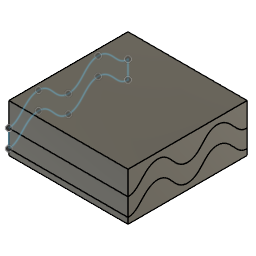
pressed block design v1 (Autodesk Fusion 360 design; units mm, degrees)
part number: 2026-06-01-15-53-17-386
Autodesk Fusion 360 part; units mm, degrees
sketch "basis" plane through (0, 0, 0) normal (1, 0, 0) x (0, 1, 0)
  spline S0 degree 5 poles (0, 0) (1.1772, 0) (3.4048, 0.3001) (6.3673, 1.6507) (9.7426, 4.9627) (13.9662, 10.0373) (18.9393, 14.1773) (25.064, 15.7986) (30.9233, 14.1773) (35.3862, 10.0373) (39.4218, 4.9627) (43.9948, 0.8227) (50, -0.7986) (56.0052, 0.8227) (60.5782, 4.9627) (64.6138, 10.0373) (69.0767, 14.1773) (74.936, 15.7986) (81.0607, 14.1773) (86.0338, 10.0373) (90.2574, 4.9627) (93.6327, 1.6507) (96.5952, 0.3001) (98.8228, 0) (100, 0) knots 0 0 0 0 0 0 0.05 0.1 0.15 0.2 0.25 0.3 0.35 0.4 0.45 0.5 0.55 0.6 0.65 0.7 0.75 0.8 0.85 0.9 0.95 1 1 1 1 1 1
  line L0 (65, 15) -> (85, 15)
  line L1 (15, 15) -> (35, 15)
  line L2 (-10, 0) -> (10, 0)
  line L3 (90, 0) -> (110, 0)
  line L4 (0, -5) -> (100, -5)
  line L5 (100, -5) -> (100, 0)
  line L6 (0, 0) -> (0, -5)
  line L7 (40, 0) -> (60, 0)
  line L8 (1.75, 0) -> (22.5, 0)
  line L9 (100, 0) -> (100, 20)
  line L10 (100, 20) -> (0, 20)
  line L11 (0, 20) -> (0, 0)
  spline S1 degree 5 poles (0, 15) (1.1772, 15) (3.4048, 15.3001) (6.3673, 16.6507) (9.7426, 19.9627) (13.9662, 25.0373) (18.9393, 29.1773) (25.064, 30.7986) (30.9233, 29.1773) (35.3862, 25.0373) (39.4218, 19.9627) (43.9948, 15.8227) (50, 14.2014) (56.0052, 15.8227) (60.5782, 19.9627) (64.6138, 25.0373) (69.0767, 29.1773) (74.936, 30.7986) (81.0607, 29.1773) (86.0338, 25.0373) (90.2574, 19.9627) (93.6327, 16.6507) (96.5952, 15.3001) (98.8228, 15) (100, 15) knots 0 0 0 0 0 0 0.05 0.1 0.15 0.2 0.25 0.3 0.35 0.4 0.45 0.5 0.55 0.6 0.65 0.7 0.75 0.8 0.85 0.9 0.95 1 1 1 1 1 1
  line L12 (-10, 15) -> (10, 15)
  line L13 (15, 30) -> (35, 30)
  line L14 (40, 15) -> (60, 15)
  line L15 (65, 30) -> (85, 30)
  line L16 (90, 15) -> (110, 15)
  point P0 (25, 15)
  point P1 (50, 0)
  point P2 (75, 15)
  point P3 (75, 30)
  point P4 (25, 30)
  point P5 (50, 15)
  dimension "d9" = 100
  dimension "d10" = 5
  dimension "d12" = 50
  dimension "wave_width" = 50
  dimension "d14" = 50
  dimension "d15" = 20
  dimension "d16" = 25
  dimension "d18" = 5
  dimension "wave_height" = 15
  dimension "d24" = 50
  dimension "d25" = 50
  dimension "d26" = 50
  dimension "d27" = 20
  dimension "d28" = 15
  constraint coincident S0.start L6.start
  constraint midpoint P2 L0
  constraint midpoint P0 L1
  constraint midpoint S0.start L2
  constraint midpoint S0.end L3
  constraint parallel L2 L4
  constraint perpendicular L4 L6
  constraint midpoint P1 L7
  constraint horizontal L1
  constraint horizontal L0
  constraint horizontal L3
  constraint horizontal L7
  constraint horizontal L2
  constraint coincident P1 L8
  constraint coincident S0.end L8
  constraint equal L0 L3
  constraint equal L0 L7
  constraint equal L1 L7
  constraint equal L1 L2
  constraint horizontal P0 P2
  constraint perpendicular L3 L9
  constraint perpendicular L9 L10
  constraint perpendicular L2 L11
  constraint midpoint P3 L15
  constraint midpoint P4 L13
  constraint midpoint S1.start L12
  constraint midpoint S1.end L16
  constraint midpoint P5 L14
  constraint horizontal L13
  constraint horizontal L15
  constraint horizontal L16
  constraint horizontal L14
  constraint horizontal L12
  constraint equal L15 L16
  constraint equal L14 L15
  constraint equal L13 L14
  constraint equal L12 L13
  constraint horizontal P3 P4
  measures "d9" distance of L4.start L4.end
  measures "d10" distance of S0.end L4.end
  measures "d12" horizontal distance of P0 P2
  measures "wave_width" distance of S0.start P1
  measures "d14" distance of S0.end P1
  measures "d15" distance of L3.start L3.end
  measures "d16" distance of S0.start P0
  measures "d18" distance of P2 L10
  measures "wave_height" distance of S0.end P2
  measures "d24" horizontal distance of P3 P4
  measures "d25" distance of S1.start P5
  measures "d26" distance of S1.end P5
  measures "d27" distance of L16.start L16.end
  measures "d28" distance of P3 S1.end
extrude "Extrude1" add sketch "basis" along normal blind 100 contours S0 L4 L5 L6 makes body 1
extrude "Extrude5" add sketch "basis" along normal up to surface (100 mm away) separate body contours S0 L9 L10 L11 S1 | L10 L11 S1 | L10 S1 | L9 L10 S1 picked at (46.6451, 18.6077) makes body 2
move_body "Move4" bodies 2 to x (1, 0, 0) y (0, 1, 0) z (0, 0, 1) at (0, 0, 15)
sketch "block" plane through (0, 0, 0) normal (1, 0, 0) x (0, 1, 0)
  spline S0 degree 5 poles (0, 15) (1.1772, 15) (3.4048, 15.3001) (6.3673, 16.6507) (9.7426, 19.9627) (13.9662, 25.0373) (18.9393, 29.1773) (25.064, 30.7986) (30.9233, 29.1773) (35.3862, 25.0373) (39.4218, 19.9627) (43.9948, 15.8227) (50, 14.2014) (56.0052, 15.8227) (60.5782, 19.9627) (64.6138, 25.0373) (69.0767, 29.1773) (74.936, 30.7986) (81.0607, 29.1773) (86.0338, 25.0373) (90.2574, 19.9627) (93.6327, 16.6507) (96.5952, 15.3001) (98.8228, 15) (100, 15) knots 0 0 0 0 0 0 0.05 0.1 0.15 0.2 0.25 0.3 0.35 0.4 0.45 0.5 0.55 0.6 0.65 0.7 0.75 0.8 0.85 0.9 0.95 1 1 1 1 1 1
  line L0 (-10, 15) -> (10, 15)
  line L1 (15, 30) -> (35, 30)
  line L2 (40, 15) -> (60, 15)
  line L3 (65, 30) -> (85, 30)
  line L4 (90, 15) -> (110, 15)
  spline S1 degree 5 poles (0, 0) (1.1772, 0) (3.4048, 0.3001) (6.3673, 1.6507) (9.7426, 4.9627) (13.9662, 10.0373) (18.9393, 14.1773) (25.064, 15.7986) (30.9233, 14.1773) (35.3862, 10.0373) (39.4218, 4.9627) (43.9948, 0.8227) (50, -0.7986) (56.0052, 0.8227) (60.5782, 4.9627) (64.6138, 10.0373) (69.0767, 14.1773) (74.936, 15.7986) (81.0607, 14.1773) (86.0338, 10.0373) (90.2574, 4.9627) (93.6327, 1.6507) (96.5952, 0.3001) (98.8228, 0) (100, 0) knots 0 0 0 0 0 0 0.05 0.1 0.15 0.2 0.25 0.3 0.35 0.4 0.45 0.5 0.55 0.6 0.65 0.7 0.75 0.8 0.85 0.9 0.95 1 1 1 1 1 1
  line L5 (-10, 0) -> (10, 0)
  line L6 (15, 15) -> (35, 15)
  line L7 (40, 0) -> (60, 0)
  line L8 (65, 15) -> (85, 15)
  line L9 (90, 0) -> (110, 0)
  line L10 (100, 15) -> (100, 0)
  line L11 (0, 15) -> (0, 0)
  point P0 (50, 15)
  point P1 (25, 30)
  point P2 (75, 30)
  point P3 (50, 0)
  point P4 (25, 15)
  point P5 (75, 15)
  dimension "d29" = 50
  dimension "d30" = 50
  dimension "d31" = 50
  dimension "d32" = 20
  dimension "d33" = 15
  dimension "d34" = 50
  dimension "d35" = 50
  dimension "d36" = 50
  dimension "d37" = 20
  dimension "d38" = 15
  constraint midpoint P2 L3
  constraint midpoint P1 L1
  constraint midpoint S0.start L0
  constraint midpoint S0.end L4
  constraint midpoint P0 L2
  constraint horizontal L1
  constraint horizontal L3
  constraint horizontal L4
  constraint horizontal L2
  constraint horizontal L0
  constraint equal L3 L4
  constraint equal L2 L3
  constraint equal L1 L2
  constraint equal L0 L1
  constraint horizontal P1 P2
  constraint midpoint P5 L8
  constraint midpoint P4 L6
  constraint midpoint S1.start L5
  constraint midpoint S1.end L9
  constraint midpoint P3 L7
  constraint horizontal L6
  constraint horizontal L8
  constraint horizontal L9
  constraint horizontal L7
  constraint horizontal L5
  constraint equal L8 L9
  constraint equal L7 L8
  constraint equal L6 L7
  constraint equal L5 L6
  constraint horizontal P4 P5
  constraint perpendicular L9 L10
  constraint perpendicular L5 L11
  measures "d29" horizontal distance of P1 P2
  measures "d30" distance of S0.start P0
  measures "d31" distance of S0.end P0
  measures "d32" distance of L4.end L4.start
  measures "d33" distance of S0.end P2
  measures "d34" horizontal distance of P4 P5
  measures "d35" distance of S1.start P3
  measures "d36" distance of S1.end P3
  measures "d37" distance of L9.end L9.start
  measures "d38" distance of S1.end P5
extrude "Extrude7" add sketch "block" along normal blind 100 separate body makes body 3
equation "d12 = wave_width"
equation "d14 = wave_width"
equation "d16 = wave_width / 2"
equation "d18 = d10"
equation "d24 = wave_width"
equation "d26 = wave_width"
equation "d29 = wave_width"
equation "d31 = wave_width"
equation "d34 = wave_width"
equation "d36 = wave_width"
named bodies: "positive", "negative", "block"
